front-wheel (Autodesk Fusion 360 design; units mm, degrees)
Autodesk Fusion 360 part; units mm, degrees
sketch "스케치1" plane through (0, 0, 0) normal (0, 1, 0) x (1, 0, 0)
  circle A0 centre (20, -10) radius 15
  dimension "d1" = 30
  measures "d1" diameter of A0
extrude "돌출1" add sketch "스케치1" along normal blind 10 makes body 1 in component "Component"
sketch "스케치2" plane through (0, 0, 0) normal (0, -1, 0) x (1, 0, 0)
  circle A0 centre (20, 10) radius 15
  circle A1 centre (20, 10) radius 2.05
  dimension "d4" = 4.1
  constraint concentric A0 A1
  measures "d4" diameter of A1
extrude "돌출2" cut sketch "스케치2" against normal blind 10 contours A1 bodies 1 in component "Component"
extrude "돌출3" cut 1 faces at (30.6199, 0, 10.8471) along direction (0, 1, 0) blind 2 on bodies 1 bodies 1 in component "Component"
extrude "돌출4" cut 1 faces at (30.6199, 2, 10.8471) along direction (0, 1, 0) blind 1 on bodies 1 bodies 1 in component "Component"
sketch "스케치3" plane through (0, 3, 0) normal (0, -1, 0) x (1, 0, 0)
  circle A0 centre (20, 10) radius 2.05
  circle A1 centre (20, 10) radius 15
  circle A2 centre (20, 10) radius 10
  line L0 (10, 10) -> (30, 10)
  line L1 (30, 10) -> (30, 30)
  line L2 (30, 30) -> (10, 30)
  line L3 (10, 30) -> (10, 10)
  dimension "d11" = 20
  dimension "d12" = 20
  dimension "d13" = 20
  constraint concentric A0 A2
  constraint horizontal L0
  constraint vertical L1
  constraint horizontal L2
  constraint vertical L3
  constraint coincident A2 L0.start
  measures "d11" diameter of A2
  measures "d12" distance of L0.start L0.end
  measures "d13" distance of L0.start L2.end
extrude "돌출1'" add sketch "스케치3" along normal blind 3 from surface at 1.5 separate body contours A0 A2 L0 | A0 A2 L0 | A1 A2 L1 L3 | A1 L1 L2 L3 picked at (20.9762, 23.2709) makes body 2 in component "Component'"
extrude "돌출1''" add sketch "스케치3" against normal blind 3 from surface at -8.5 separate body contours A0 A2 L0 | A0 A2 L0 | A1 A2 L1 L3 | A1 L1 L2 L3 picked at (20.9762, 23.2709) makes body 3 in component "Component''"
sketch "스케치4" plane through (0, 0, 30) normal (0, 0, 1) x (-1, 0, 0)
  line L0 (-30, -1.5) -> (-10, -1.5)
  line L1 (-10, -1.5) -> (-10, 1.5)
  line L2 (-10, 1.5) -> (-30, 1.5)
  line L3 (-30, 1.5) -> (-30, -1.5)
  line L4 (-25, 1.5) -> (-15, 1.5)
  line L5 (-15, 1.5) -> (-15, -1.5)
  line L6 (-15, -1.5) -> (-25, -1.5)
  line L7 (-25, -1.5) -> (-25, 1.5)
  dimension "d20" = 10
  dimension "d21" = 5
  constraint horizontal L4
  constraint vertical L5
  constraint horizontal L6
  constraint vertical L7
  constraint coincident L2 L4.start
  measures "d20" distance of L4.start L4.end
  measures "d21" distance of L1 L5
extrude "돌출2'" add sketch "스케치4" along normal blind 3 contours L0 L2 L4 L5 L6 L7 bodies 2 in component "Component'"
sketch "스케치5" plane through (0, 0, 30) normal (0, 0, 1) x (-1, 0, 0)
  line L0 (-10, -11.5) -> (-30, -11.5)
  line L1 (-30, -11.5) -> (-30, -14.5)
  line L2 (-30, -14.5) -> (-10, -14.5)
  line L3 (-10, -14.5) -> (-10, -11.5)
  line L4 (-15, -11.5) -> (-25, -11.5)
  line L5 (-25, -11.5) -> (-25, -14.5)
  line L6 (-25, -14.5) -> (-15, -14.5)
  line L7 (-15, -14.5) -> (-15, -11.5)
  dimension "d24" = 10
  dimension "d25" = 5
  constraint horizontal L4
  constraint vertical L5
  constraint horizontal L6
  constraint vertical L7
  constraint coincident L0 L4.start
  measures "d24" distance of L4.start L4.end
  measures "d25" distance of L3 L7
extrude "돌출2''" add sketch "스케치5" along normal blind 3 contours L0 L2 L4 L5 L6 L7 bodies 3 in component "Component''"
sketch "스케치6" plane through (0, 0, 33) normal (0, 0, 1) x (-1, 0, 0)
  line L0 (-25, -1.5) -> (-15, -1.5)
  line L1 (-15, -1.5) -> (-15, 1.5)
  line L2 (-15, 1.5) -> (-25, 1.5)
  line L3 (-25, 1.5) -> (-25, -1.5)
  line L4 (-30, 5.5) -> (-10, 5.5)
  line L5 (-10, 5.5) -> (-10, -18.5)
  line L6 (-10, -18.5) -> (-30, -18.5)
  line L7 (-30, -18.5) -> (-30, 5.5)
  line L8 (-25, -14.5) -> (-15, -14.5)
  circle A0 centre (-20, -6.5) radius 2.05
  line L9 (-25, -14.5) -> (-15, -14.5)
  line L10 (-15, -14.5) -> (-15, -11.5)
  line L11 (-15, -11.5) -> (-25, -11.5)
  line L12 (-25, -11.5) -> (-25, -14.5)
  dimension "d28" = 20
  dimension "d29" = 4
  dimension "d30" = 4
  dimension "d31" = 4.1
  dimension "d32" = 5
  dimension "d33" = 3
  constraint horizontal L4
  constraint vertical L5
  constraint horizontal L6
  constraint vertical L7
  constraint horizontal L9
  constraint vertical L10
  constraint horizontal L11
  constraint vertical L12
  constraint coincident L8.start L9.start
  measures "d28" distance of L4.start L4.end
  measures "d29" distance of L2 L4
  measures "d30" distance of L6 L8
  measures "d31" diameter of A0
  measures "d32" distance of L0 A0.centre
  measures "d33" distance of L8.start L11.end
extrude "돌출1'''" add sketch "스케치6" against normal blind 3 separate body makes body 4 in component "Component'''"
sketch "스케치7" plane through (0, 0, 33) normal (0, 0, 1) x (-1, 0, 0)
  line L0 (-25, -14.5) -> (-25, -11.5)
  line L1 (-25, -11.5) -> (-15, -11.5)
  line L2 (-15, -11.5) -> (-15, -14.5)
  line L3 (-15, -14.5) -> (-25, -14.5)
  circle A0 centre (-20, -6.5) radius 2.05
  line L4 (-25, -1.5) -> (-25, 1.5)
  line L5 (-25, 1.5) -> (-15, 1.5)
  line L6 (-15, 1.5) -> (-15, -1.5)
  line L7 (-15, -1.5) -> (-25, -1.5)
  line L8 (-30, -18.5) -> (-10, -18.5)
  line L9 (-10, -18.5) -> (-10, 5.5)
  line L10 (-10, 5.5) -> (-30, 5.5)
  line L11 (-30, 5.5) -> (-30, -18.5)
  circle A1 centre (-20, -6.5) radius 10
  dimension "d36" = 20
  constraint concentric A0 A1
  measures "d36" diameter of A1
extrude "돌출2'''" cut sketch "스케치7" against normal blind 3 contours L8 L9 L11 A1 | L9 L10 L11 A1 bodies 4 in component "Component'''"
component "Component" placed x (1, 0, 0) y (0, 1, 0) z (0, 0, 1) at (0, 0, 0)
component "Component'" placed x (1, 0, 0) y (0, 1, 0) z (0, 0, 1) at (0, 0, 0)
component "Component''" placed x (1, 0, 0) y (0, 1, 0) z (0, 0, 1) at (0, 0, 0)
component "Component'''" placed x (1, 0, 0) y (0, 1, 0) z (0, 0, 1) at (0, 0, 0)
component "Component'" placed x (1, 0, 0) y (0, -1, 0) z (0, 0, -1) at (22.9778, 0, 68.7681)
component "Component''" placed x (1, 0, 0) y (0, -1, 0) z (0, 0, -1) at (0, 0, 68.6942)
component "Component'''" placed x (1, 0, 0) y (0, 0, -1) z (0, 1, 0) at (-21.574, -38, 51.6736)
